Autodesk Fusion 360 part; units mm, degrees
(part 3 of 3)
equation "oledW = 35.4 mm" comment "Handson Technology DSP1170 PCB width, page 2"
equation "oledH = 33.5 mm" comment "Handson Technology DSP1170 PCB height, page 2"
equation "oledT = 1.2 mm" comment "Nominal OLED PCB thickness"
equation "oledHoleX = oledW - 5 mm" comment "Handson drawing hole centers 2.5 mm from each side"
equation "oledHoleY = oledH - 5 mm" comment "Handson drawing hole centers 2.5 mm from each end"
equation "oledHoleD = 2.5 mm" comment "Handson drawing mounting hole radius 1.25 mm"
equation "oledHoleCY = 0 mm" comment "Handson centered mounting-hole rectangle"
equation "oledGlassW = 34.5 mm" comment "Approximate glass width from Handson page 2 projection"
equation "oledGlassH = 23 mm" comment "Approximate glass height from Handson page 2 projection"
equation "oledGlassY = 0 mm" comment "Centered from Handson page 2 projection"
equation "oledGlassStack = 1.9 mm" comment "Glass plus adhesive above PCB, nominal"
equation "oledActiveW = 29.42 mm" comment "SH1106 1.3-inch nominal active width"
equation "oledActiveH = 14.70 mm" comment "SH1106 1.3-inch nominal active height"
equation "oledActiveY = -1.8 mm" comment "Estimated visible area offset from Handson front image"
equation "oledPadPitch = 2.54 mm" comment "Nominal pitch from Handson four-pad row"
equation "oledPadY = oledH / 2 - 2 mm" comment "Handson pad row center 2 mm from PCB top"
equation "wireStack = 1 mm" comment "User estimate for soldered wire protrusion"
equation "windowW = oledActiveW + 1.8 mm" comment "Pixel mask includes alignment allowance"
equation "windowH = oledActiveH + 1.8 mm" comment "Pixel mask includes alignment allowance"
equation "screenSetback = 3.2 mm" comment "Deeper sloped reveal for long screws, PCB unchanged in XY"
equation "glassGap = 0.2 mm" comment "Equals setback for full through-opening around glass"
equation "glassXYGap = 0.30 mm" comment "Clearance around glass edges"
equation "wall = 1.6 mm" comment "Outer shell wall thickness"
equation "boardGap = 0.25 mm" comment "ESP32 PCB end clearance per side"
equation "oledSideGap = 0.25 mm" comment "OLED PCB to wall clearance per side"
equation "caseW = espL + 2 * wall + 2 * boardGap" comment "Width set by the ESP32 and shell"
equation "caseH = oledH + 2 * wall + 2 * oledSideGap" comment "Height set by OLED and shell"
equation "caseD = 18.55 mm" comment "Allows stock screw range 6-8 mm under head above the ESP32"
equation "frontSkin = 4.6 mm" comment "Extra blind-pilot depth accommodates both interpretations of reported 8 mm screw height"
equation "rearT = 1.55 mm" comment "Rear plate thickness and assembly seam"
equation "cornerR = 2.8 mm" comment "Matched outer corners"
equation "frontEdgeR = 0.5 mm" comment "Front outside roundover"
equation "rearEdgeR = 0.35 mm" comment "Rear outside roundover"
equation "m2Pilot = 1.7 mm" comment "Trial diameter for threads formed in printed plastic"
equation "m2Clear = 2.35 mm" comment "Screw clearance through rear supports"
equation "m2HeadD = 4.3 mm" comment "Recess diameter allowance, check stock head"
equation "m2HeadZ = 2.85 mm" comment "Deeper rear head seat allows 2-4 mm thread engagement for 6-8 mm shanks"
equation "m2Length = 8 mm" comment "Nominal screw length under head"
equation "m2TipGap = 0.45 mm" comment "Blind screw hole tip clearance"
equation "m2BossD = 5.2 mm" comment "Front screw boss diameter"
equation "espPostD = 4.4 mm" comment "Rear spacer fits the PCB mounting land"
equation "espFootD = 6 mm" comment "Wider screw recess floor support"
equation "espFootZ = 3.55 mm" comment "Thicker counterbore roof, switch-side clearance removed locally"
equation "espClampGap = 0.1 mm" comment "Avoids crushing ESP PCB at seam, shim if needed"
equation "oledPadD = 4.6 mm" comment "Four load-bearing bosses around the actual OLED mounting holes"
equation "oledSeat = caseD - screenSetback - oledGlassStack" comment "OLED PCB front face"
equation "oledRear = oledSeat - oledT" comment "OLED PCB back, nominal 2.5 mm from ESP PCB"
equation "clampGap = 0.12 mm" comment "Positive closing clearance; thin compressible shim as needed"
equation "clampX = oledW / 2 - 4.9 mm" comment "OLED clamp pads near PCB corners clear central header"
equation "clampW = 4.8 mm" comment "Width of OLED retaining fingers"
equation "clampInnerY = oledH / 2 - 1.8 mm" comment "Clamp overlap with OLED PCB"
equation "clampOuterY = caseH / 2 - wall - 0.24 mm" comment "Clamp outer wall clearance"
equation "keyGap = 0.25 mm" comment "Rear locating key to shell clearance"
equation "d79 = rearT"
equation "d81 = -( -caseW / 2 )"
equation "d82 = -( -caseH / 2 )"
equation "d83 = caseW"
equation "d84 = caseH"
equation "d85 = caseD - rearT"
equation "d88 = cornerR"
equation "d90 = frontEdgeR"
equation "d91 = rearT"
equation "d93 = -( -caseW / 2 + wall )"
equation "d94 = -( -caseH / 2 + wall )"
equation "d95 = caseW - 2 * wall"
equation "d96 = caseH - 2 * wall"
equation "d97 = caseD - frontSkin - rearT"
equation "d100 = cornerR - wall"
equation "d101 = caseD - frontSkin"
equation "d103 = -( -oledGlassW / 2 - glassXYGap )"
equation "d104 = -( oledGlassY - oledGlassH / 2 - glassXYGap )"
equation "d105 = oledGlassW + 2 * glassXYGap"
equation "d106 = oledGlassH + 2 * glassXYGap"
equation "d107 = frontSkin - screenSetback + glassGap"
equation "d109 = caseD - screenSetback + glassGap"
equation "d111 = -( -windowW / 2 )"
equation "d112 = -( oledActiveY - windowH / 2 )"
equation "d113 = windowW"
equation "d114 = windowH"
equation "d117 = oledSeat"
equation "d119 = -( -oledHoleX / 2 )"
equation "d120 = -( oledHoleCY - oledHoleY / 2 )"
equation "d121 = oledPadD"
equation "d122 = caseD - frontSkin - oledSeat"
equation "d124 = oledSeat"
equation "d126 = -( -oledHoleX / 2 )"
equation "d127 = ( oledHoleCY + oledHoleY / 2 )"
equation "d128 = oledPadD"
equation "d129 = caseD - frontSkin - oledSeat"
equation "d131 = oledSeat"
equation "d133 = ( oledHoleX / 2 )"
equation "d134 = -( oledHoleCY - oledHoleY / 2 )"
equation "d135 = oledPadD"
equation "d136 = caseD - frontSkin - oledSeat"
equation "d138 = oledSeat"
equation "d140 = ( oledHoleX / 2 )"
equation "d141 = ( oledHoleCY + oledHoleY / 2 )"
equation "d142 = oledPadD"
equation "d143 = caseD - frontSkin - oledSeat"
equation "d145 = oledRear - 0.35 mm"
equation "d147 = -( -oledW / 2 - oledSideGap - 1.5 mm )"
equation "d148 = -( -10.5 mm )"
equation "d151 = caseD - frontSkin - oledRear + 0.35 mm"
equation "d153 = oledRear - 0.35 mm"
equation "d155 = -( -oledW / 2 - oledSideGap - 1.5 mm )"
equation "d156 = ( 6.5 mm )"
equation "d159 = caseD - frontSkin - oledRear + 0.35 mm"
equation "d161 = oledRear - 0.35 mm"
equation "d163 = ( oledW / 2 + oledSideGap )"
equation "d164 = -( -10.5 mm )"
equation "d167 = caseD - frontSkin - oledRear + 0.35 mm"
equation "d169 = oledRear - 0.35 mm"
equation "d171 = ( oledW / 2 + oledSideGap )"
equation "d172 = ( 6.5 mm )"
equation "d175 = caseD - frontSkin - oledRear + 0.35 mm"
equation "d177 = espBack + espClampGap"
equation "d179 = -( -espHoleX / 2 )"
equation "d180 = -( -espHoleY / 2 )"
equation "d181 = m2BossD"
equation "d182 = caseD - frontSkin - espBack - espClampGap"
equation "d184 = espBack + espClampGap"
equation "d186 = -( -espHoleX / 2 )"
equation "d187 = ( espHoleY / 2 )"
equation "d188 = m2BossD"
equation "d189 = caseD - frontSkin - espBack - espClampGap"
equation "d191 = espBack + espClampGap"
equation "d193 = ( espHoleX / 2 )"
equation "d194 = -( -espHoleY / 2 )"
equation "d195 = m2BossD"
equation "d196 = caseD - frontSkin - espBack - espClampGap"
equation "d198 = espBack + espClampGap"
equation "d200 = ( espHoleX / 2 )"
equation "d201 = ( espHoleY / 2 )"
equation "d202 = m2BossD"
equation "d203 = caseD - frontSkin - espBack - espClampGap"
equation "d205 = espBack + espClampGap"
equation "d207 = -( -caseW / 2 + wall - 0.2 mm )"
equation "d208 = -( -espHoleY / 2 - 1.45 mm )"
equation "d209 = caseW / 2 - wall - espHoleX / 2 + 0.2 mm"
equation "d211 = caseD - frontSkin - espBack - espClampGap"
equation "d213 = espBack + espClampGap"
equation "d215 = -( -caseW / 2 + wall - 0.2 mm )"
equation "d216 = ( espHoleY / 2 - 1.45 mm )"
equation "d217 = caseW / 2 - wall - espHoleX / 2 + 0.2 mm"
equation "d219 = caseD - frontSkin - espBack - espClampGap"
equation "d221 = espBack + espClampGap"
equation "d223 = ( espHoleX / 2 )"
equation "d224 = -( -espHoleY / 2 - 1.45 mm )"
equation "d225 = caseW / 2 - wall - espHoleX / 2 + 0.2 mm"
equation "d227 = caseD - frontSkin - espBack - espClampGap"
equation "d229 = espBack + espClampGap"
equation "d231 = ( espHoleX / 2 )"
equation "d232 = ( espHoleY / 2 - 1.45 mm )"
equation "d233 = caseW / 2 - wall - espHoleX / 2 + 0.2 mm"
equation "d235 = caseD - frontSkin - espBack - espClampGap"
equation "d237 = espBack + espClampGap"
equation "d239 = -( -espHoleX / 2 )"
equation "d240 = -( -espHoleY / 2 )"
equation "d241 = m2Pilot"
equation "d242 = m2HeadZ + m2Length + m2TipGap - espBack - espClampGap"
equation "d244 = espBack + espClampGap"
equation "d246 = -( -espHoleX / 2 )"
equation "d247 = ( espHoleY / 2 )"
equation "d248 = m2Pilot"
equation "d249 = m2HeadZ + m2Length + m2TipGap - espBack - espClampGap"
equation "d251 = espBack + espClampGap"
equation "d253 = ( espHoleX / 2 )"
equation "d254 = -( -espHoleY / 2 )"
equation "d255 = m2Pilot"
equation "d256 = m2HeadZ + m2Length + m2TipGap - espBack - espClampGap"
equation "d258 = espBack + espClampGap"
equation "d260 = ( espHoleX / 2 )"
equation "d261 = ( espHoleY / 2 )"
equation "d262 = m2Pilot"
equation "d263 = m2HeadZ + m2Length + m2TipGap - espBack - espClampGap"
equation "d265 = rearT"
equation "d267 = ( caseW / 2 - wall - 1.7 mm )"
equation "d268 = -( usbY - usbOpeningW / 2 )"
equation "d269 = wall + 2.7 mm"
equation "d270 = usbOpeningW"
equation "d271 = usbSlotTop - rearT"
equation "d273 = -( -caseW / 2 )"
equation "d274 = -( -caseH / 2 )"
equation "d275 = caseW"
equation "d276 = caseH"
equation "d277 = rearT"
equation "d280 = cornerR"
equation "d282 = rearEdgeR"
equation "d283 = rearT"
equation "d285 = -( -espHoleX / 2 )"
equation "d286 = -( -espHoleY / 2 )"
equation "d287 = espFootD"
equation "d288 = espFootZ - rearT"
equation "d290 = rearT"
equation "d292 = -( -espHoleX / 2 )"
equation "d293 = ( espHoleY / 2 )"
equation "d294 = espFootD"
equation "d295 = espFootZ - rearT"
equation "d297 = rearT"
equation "d299 = ( espHoleX / 2 )"
equation "d300 = -( -espHoleY / 2 )"
equation "d301 = espFootD"
equation "d302 = espFootZ - rearT"
equation "d304 = rearT"
equation "d306 = ( espHoleX / 2 )"
equation "d307 = ( espHoleY / 2 )"
equation "d308 = espFootD"
equation "d309 = espFootZ - rearT"
equation "d311 = espFootZ"
equation "d313 = -( -espHoleX / 2 )"
equation "d314 = -( -espHoleY / 2 )"
equation "d315 = espPostD"
equation "d316 = espSeat - espFootZ"
equation "d318 = espFootZ"
equation "d320 = -( -espHoleX / 2 )"
equation "d321 = ( espHoleY / 2 )"
equation "d322 = espPostD"
equation "d323 = espSeat - espFootZ"
equation "d325 = espFootZ"
equation "d327 = ( espHoleX / 2 )"
equation "d328 = -( -espHoleY / 2 )"
equation "d329 = espPostD"
equation "d330 = espSeat - espFootZ"
equation "d332 = espFootZ"
equation "d334 = ( espHoleX / 2 )"
equation "d335 = ( espHoleY / 2 )"
equation "d336 = espPostD"
equation "d337 = espSeat - espFootZ"
equation "d339 = -( -espHoleX / 2 )"
equation "d340 = -( -espHoleY / 2 )"
equation "d341 = m2Clear"
equation "d342 = espSeat"
equation "d344 = -( -espHoleX / 2 )"
equation "d345 = ( espHoleY / 2 )"
equation "d346 = m2Clear"
equation "d347 = espSeat"
equation "d349 = ( espHoleX / 2 )"
equation "d350 = -( -espHoleY / 2 )"
equation "d351 = m2Clear"
equation "d352 = espSeat"
equation "d354 = ( espHoleX / 2 )"
equation "d355 = ( espHoleY / 2 )"
equation "d356 = m2Clear"
equation "d357 = espSeat"
equation "d359 = -( -espHoleX / 2 )"
equation "d360 = -( -espHoleY / 2 )"
equation "d361 = m2HeadD"
equation "d362 = m2HeadZ"
equation "d364 = -( -espHoleX / 2 )"
equation "d365 = ( espHoleY / 2 )"
equation "d366 = m2HeadD"
equation "d367 = m2HeadZ"
equation "d369 = ( espHoleX / 2 )"
equation "d370 = -( -espHoleY / 2 )"
equation "d371 = m2HeadD"
equation "d372 = m2HeadZ"
equation "d374 = ( espHoleX / 2 )"
equation "d375 = ( espHoleY / 2 )"
equation "d376 = m2HeadD"
equation "d377 = m2HeadZ"
equation "d379 = rearT"
equation "d381 = ( espL / 2 - bootInset )"
equation "d382 = -( bootY )"
equation "d383 = buttonGuideD"
equation "d384 = espSeat - espButtonH - buttonGap - rearT"
equation "d386 = ( espL / 2 - bootInset )"
equation "d387 = -( bootY )"
equation "d388 = buttonBore"
equation "d389 = espSeat - espButtonH - buttonGap"
equation "d391 = rearT"
equation "d393 = ( espL / 2 - enableInset )"
equation "d394 = ( enableY )"
equation "d395 = buttonGuideD"
equation "d396 = espSeat - espButtonH - buttonGap - rearT"
equation "d398 = ( espL / 2 - enableInset )"
equation "d399 = ( enableY )"
equation "d400 = buttonBore"
equation "d401 = espSeat - espButtonH - buttonGap"
equation "d403 = rearT"
equation "d405 = -( -clampX - clampW / 2 )"
equation "d406 = -( -clampOuterY )"
equation "d407 = clampW"
equation "d408 = clampOuterY - clampInnerY"
equation "d411 = rearT"
equation "d413 = ( clampX - clampW / 2 )"
equation "d414 = -( -clampOuterY )"
equation "d415 = clampW"
equation "d416 = clampOuterY - clampInnerY"
equation "d419 = rearT"
equation "d421 = -( -clampX - clampW / 2 )"
equation "d422 = ( clampInnerY )"
equation "d423 = clampW"
equation "d424 = clampOuterY - clampInnerY"
equation "d427 = rearT"
equation "d429 = ( clampX - clampW / 2 )"
equation "d430 = ( clampInnerY )"
equation "d431 = clampW"
equation "d432 = clampOuterY - clampInnerY"
equation "d435 = rearT"
equation "d437 = -( -18.5 mm )"
equation "d438 = -( -espW / 2 - 1.4 mm )"
equation "d441 = espBack - 0.1 mm - rearT"
equation "d443 = rearT"
equation "d445 = ( 15.5 mm )"
equation "d446 = -( -espW / 2 - 1.4 mm )"
equation "d449 = espBack - 0.1 mm - rearT"
equation "d451 = rearT"
equation "d453 = -( -18.5 mm )"
equation "d454 = ( espW / 2 + 0.2 mm )"
equation "d457 = espBack - 0.1 mm - rearT"
equation "d459 = rearT"
equation "d461 = ( 15.5 mm )"
equation "d462 = ( espW / 2 + 0.2 mm )"
equation "d465 = espBack - 0.1 mm - rearT"
equation "d467 = rearT"
equation "d469 = -( -caseW / 2 + wall + keyGap )"
equation "d470 = caseH / 2 - wall - 1.55 mm"
equation "d475 = rearT"
equation "d477 = -( -caseW / 2 + wall + keyGap )"
equation "d478 = caseH / 2 - wall - 4.15 mm"
equation "d483 = rearT"
equation "d485 = ( caseW / 2 - wall - keyGap - 1.25 mm )"
equation "d486 = caseH / 2 - wall - 1.55 mm"
equation "d491 = rearT"
equation "d493 = ( caseW / 2 - wall - keyGap - 1.25 mm )"
equation "d494 = caseH / 2 - wall - 4.15 mm"
equation "d499 = ( caseW / 2 - usbRearRelief )"
equation "d500 = -( usbY - usbOpeningW / 2 )"
equation "d501 = usbRearRelief + 1 mm"
equation "d502 = usbOpeningW"
equation "d503 = rearT"
equation "d505 = oledRear"
equation "d507 = -( -oledW / 2 )"
equation "d508 = -( -oledH / 2 )"
equation "d509 = oledW"
equation "d510 = oledH"
equation "d511 = oledT"
equation "d513 = oledRear"
equation "d515 = -( -oledHoleX / 2 )"
equation "d516 = -( oledHoleCY - oledHoleY / 2 )"
equation "d517 = oledHoleD"
equation "d518 = oledT"
equation "d520 = oledRear"
equation "d522 = -( -oledHoleX / 2 )"
equation "d523 = ( oledHoleCY + oledHoleY / 2 )"
equation "d524 = oledHoleD"
equation "d525 = oledT"
equation "d527 = oledRear"
equation "d529 = ( oledHoleX / 2 )"
equation "d530 = -( oledHoleCY - oledHoleY / 2 )"
equation "d531 = oledHoleD"
equation "d532 = oledT"
equation "d534 = oledRear"
equation "d536 = ( oledHoleX / 2 )"
equation "d537 = ( oledHoleCY + oledHoleY / 2 )"
equation "d538 = oledHoleD"
equation "d539 = oledT"
equation "d541 = oledSeat"
equation "d543 = -( -oledGlassW / 2 )"
equation "d544 = -( oledGlassY - oledGlassH / 2 )"
equation "d545 = oledGlassW"
equation "d546 = oledGlassH"
equation "d547 = oledGlassStack"
equation "d549 = oledRear - wireStack"
equation "d551 = -( -2 * oledPadPitch )"
equation "d552 = ( oledPadY - 1.2 mm )"
equation "d553 = 4 * oledPadPitch"
equation "d555 = wireStack"
equation "d557 = espSeat"
equation "d559 = -( -espL / 2 )"
equation "d560 = -( -espW / 2 )"
equation "d561 = espL"
equation "d562 = espW"
equation "d563 = espT"
equation "d565 = espSeat"
equation "d567 = -( -espHoleX / 2 )"
equation "d568 = -( -espHoleY / 2 )"
equation "d569 = espHoleD"
equation "d570 = espT"
equation "d572 = espSeat"
equation "d574 = -( -espHoleX / 2 )"
equation "d575 = ( espHoleY / 2 )"
equation "d576 = espHoleD"
equation "d577 = espT"
equation "d579 = espSeat"
equation "d581 = ( espHoleX / 2 )"
equation "d582 = -( -espHoleY / 2 )"
equation "d583 = espHoleD"
equation "d584 = espT"
equation "d586 = espSeat"
equation "d588 = ( espHoleX / 2 )"
equation "d589 = ( espHoleY / 2 )"
equation "d590 = espHoleD"
equation "d591 = espT"
equation "d593 = espSeat - espPartH"
equation "d595 = -( -espL / 2 + espAntennaL )"
equation "d596 = -( -9 mm )"
equation "d597 = 25.5 mm - espAntennaL"
equation "d599 = espPartH"
equation "d601 = espSeat - 0.9 mm"
equation "d603 = -( -espL / 2 )"
equation "d604 = -( -9 mm )"
equation "d605 = espAntennaL"
equation "d609 = espSeat - usbShellH"
equation "d611 = ( espL / 2 - 6.2 mm )"
equation "d612 = -( usbY - usbShellW / 2 )"
equation "d613 = 6.2 mm + usbProtrusion"
equation "d614 = usbShellW"
equation "d615 = usbShellH"
equation "d617 = espSeat - espButtonH"
equation "d619 = ( espL / 2 - bootInset - 1.8 mm )"
equation "d620 = -( bootY - 1.3 mm )"
equation "d623 = espButtonH"
equation "d625 = espSeat - espButtonH"
equation "d627 = ( espL / 2 - enableInset - 1.8 mm )"
equation "d628 = ( enableY - 1.3 mm )"
equation "d631 = espButtonH"
equation "displayBevel = 2.65 mm" comment "45 degree sloped display surround, 0.35 mm straight throat"
equation "oledScrewL = 8 mm" comment "Upper end of 6-8 mm under-head stock design range, not a measured shank"
equation "oledScrewHeadH = 2 mm" comment "Maximum modeled OLED screw head height"
equation "oledScrewHeadD = 4 mm" comment "Maximum modeled OLED screw head diameter"
equation "oledPilotDepth = 4.1 mm" comment "Up to 3.8 mm engagement plus 0.3 mm tip clearance"
equation "d638 = caseD - screenSetback + glassGap"
equation "d640 = -( -windowW / 2 )"
equation "d641 = -( oledActiveY - windowH / 2 )"
equation "d642 = windowW"
equation "d643 = windowH"
equation "d644 = screenSetback - glassGap"
equation "d646 = oledSeat"
equation "d648 = -( -oledHoleX / 2 )"
equation "d649 = -( oledHoleCY - oledHoleY / 2 )"
equation "d650 = m2Pilot"
equation "d651 = oledPilotDepth"
equation "d653 = oledSeat"
equation "d655 = -( -oledHoleX / 2 )"
equation "d656 = ( oledHoleCY + oledHoleY / 2 )"
equation "d657 = m2Pilot"
equation "d658 = oledPilotDepth"
equation "d660 = oledSeat"
equation "d662 = ( oledHoleX / 2 )"
equation "d663 = -( oledHoleCY - oledHoleY / 2 )"
equation "d664 = m2Pilot"
equation "d665 = oledPilotDepth"
equation "d667 = oledSeat"
equation "d669 = ( oledHoleX / 2 )"
equation "d670 = ( oledHoleCY + oledHoleY / 2 )"
equation "d671 = m2Pilot"
equation "d672 = oledPilotDepth"
equation "d674 = displayBevel"
equation "d675 = oledRear - oledSpacerH - oledScrewHeadH"
equation "d677 = -( -oledHoleX / 2 )"
equation "d678 = -( oledHoleCY - oledHoleY / 2 )"
equation "d679 = oledScrewHeadD"
equation "d680 = oledScrewHeadH"
equation "d682 = oledRear - oledSpacerH"
equation "d684 = -( -oledHoleX / 2 )"
equation "d685 = -( oledHoleCY - oledHoleY / 2 )"
equation "d687 = oledScrewL"
equation "d689 = oledRear - oledSpacerH - oledScrewHeadH"
equation "d691 = -( -oledHoleX / 2 )"
equation "d692 = ( oledHoleCY + oledHoleY / 2 )"
equation "d693 = oledScrewHeadD"
equation "d694 = oledScrewHeadH"
equation "d696 = oledRear - oledSpacerH"
equation "d698 = -( -oledHoleX / 2 )"
equation "d699 = ( oledHoleCY + oledHoleY / 2 )"
equation "d701 = oledScrewL"
equation "d703 = oledRear - oledSpacerH - oledScrewHeadH"
equation "d705 = ( oledHoleX / 2 )"
equation "d706 = -( oledHoleCY - oledHoleY / 2 )"
equation "d707 = oledScrewHeadD"
equation "d708 = oledScrewHeadH"
equation "d710 = oledRear - oledSpacerH"
equation "d712 = ( oledHoleX / 2 )"
equation "d713 = -( oledHoleCY - oledHoleY / 2 )"
equation "d715 = oledScrewL"
equation "d717 = oledRear - oledSpacerH - oledScrewHeadH"
equation "d719 = ( oledHoleX / 2 )"
equation "d720 = ( oledHoleCY + oledHoleY / 2 )"
equation "d721 = oledScrewHeadD"
equation "d722 = oledScrewHeadH"
equation "d724 = oledRear - oledSpacerH"
equation "d726 = ( oledHoleX / 2 )"
equation "d727 = ( oledHoleCY + oledHoleY / 2 )"
equation "d729 = oledScrewL"
equation "oledSpacerH = 3 mm" comment "Separate printed spacers beneath PCB for long stock screws"
equation "oledSpacerD = 4.6 mm" comment "Spacer mounting land diameter"
equation "oledSpacerBarH = 1.4 mm" comment "Connects a pair of spacers into one printable rail"
equation "wireFrontH = oledGlassStack" comment "User says cable connections rise approximately as high as glass"
equation "wireRoofGap = 0.3 mm" comment "Clearance above front-facing soldered wires"
equation "wirePocketW = 13 mm" comment "Four 2.54 mm-pitch wires plus side clearance"
equation "wirePocketY = oledGlassY + oledGlassH / 2 - 0.2 mm" comment "Joins cable clearance to glass recess without pinching the bend"
equation "wirePocketEndY = oledH / 2 + 0.25 mm" comment "Wire relief terminates inside shell side wall"
equation "d739 = oledRear - oledSpacerH"
equation "d741 = -( -oledHoleX / 2 )"
equation "d742 = -( oledHoleCY - oledHoleY / 2 )"
equation "d744 = oledHoleY"
equation "d745 = oledSpacerBarH"
equation "d747 = oledRear - oledSpacerH"
equation "d749 = -( -1 * oledHoleX / 2 )"
equation "d750 = -( oledHoleCY - oledHoleY / 2 )"
equation "d751 = oledSpacerD"
equation "d752 = oledSpacerH"
equation "d754 = oledRear - oledSpacerH"
equation "d756 = -( -1 * oledHoleX / 2 )"
equation "d757 = ( oledHoleCY + oledHoleY / 2 )"
equation "d758 = oledSpacerD"
equation "d759 = oledSpacerH"
equation "d761 = oledRear - oledSpacerH"
equation "d763 = -( -1 * oledHoleX / 2 )"
equation "d764 = -( oledHoleCY - oledHoleY / 2 )"
equation "d765 = m2Clear"
equation "d766 = oledSpacerH"
equation "d768 = oledRear - oledSpacerH"
equation "d770 = -( -1 * oledHoleX / 2 )"
equation "d771 = ( oledHoleCY + oledHoleY / 2 )"
equation "d772 = m2Clear"
equation "d773 = oledSpacerH"
equation "d775 = oledRear - oledSpacerH"
equation "d777 = ( oledHoleX / 2 - 2.1 mm )"
equation "d778 = -( oledHoleCY - oledHoleY / 2 )"
equation "d780 = oledHoleY"
equation "d781 = oledSpacerBarH"
equation "d783 = oledRear - oledSpacerH"
equation "d785 = ( 1 * oledHoleX / 2 )"
equation "d786 = -( oledHoleCY - oledHoleY / 2 )"
equation "d787 = oledSpacerD"
equation "d788 = oledSpacerH"
equation "d790 = oledRear - oledSpacerH"
equation "d792 = ( 1 * oledHoleX / 2 )"
equation "d793 = ( oledHoleCY + oledHoleY / 2 )"
equation "d794 = oledSpacerD"
equation "d795 = oledSpacerH"
equation "d797 = oledRear - oledSpacerH"
equation "d799 = ( 1 * oledHoleX / 2 )"
equation "d800 = -( oledHoleCY - oledHoleY / 2 )"
equation "d801 = m2Clear"
equation "d802 = oledSpacerH"
equation "d804 = oledRear - oledSpacerH"
equation "d806 = ( 1 * oledHoleX / 2 )"
equation "d807 = ( oledHoleCY + oledHoleY / 2 )"
equation "d808 = m2Clear"
equation "d809 = oledSpacerH"
equation "d811 = caseD - frontSkin"
equation "d813 = -( -wirePocketW / 2 )"
equation "d814 = ( wirePocketY )"
equation "d815 = wirePocketW"
equation "d816 = wirePocketEndY - wirePocketY"
equation "d817 = oledSeat + wireFrontH + wireRoofGap - caseD + frontSkin"
equation "d819 = oledSeat"
equation "d821 = -( -2 * oledPadPitch )"
equation "d822 = ( oledPadY - 1.2 mm )"
equation "d823 = 4 * oledPadPitch"
equation "d825 = wireFrontH"
equation "d827 = espSeat - espButtonH - 0.05 mm"
equation "d829 = ( espL / 2 - bootInset - 2.2 mm )"
equation "d830 = -( bootY - 1.55 mm )"
equation "d833 = espFootZ - espSeat + espButtonH + 0.05 mm"
equation "d835 = espSeat - espButtonH - 0.05 mm"
equation "d837 = ( espL / 2 - bootInset - 2.2 mm )"
equation "d838 = ( enableY - 1.55 mm )"
equation "d841 = espFootZ - espSeat + espButtonH + 0.05 mm"
equation "d843 = m2HeadZ - oledScrewHeadH"
equation "d845 = -( -espHoleX / 2 )"
equation "d846 = -( -espHoleY / 2 )"
equation "d847 = oledScrewHeadD"
equation "d848 = oledScrewHeadH"
equation "d850 = m2HeadZ"
equation "d852 = -( -espHoleX / 2 )"
equation "d853 = -( -espHoleY / 2 )"
equation "d855 = m2Length"
equation "d857 = m2HeadZ - oledScrewHeadH"
equation "d859 = -( -espHoleX / 2 )"
equation "d860 = ( espHoleY / 2 )"
equation "d861 = oledScrewHeadD"
equation "d862 = oledScrewHeadH"
equation "d864 = m2HeadZ"
equation "d866 = -( -espHoleX / 2 )"
equation "d867 = ( espHoleY / 2 )"
equation "d869 = m2Length"
equation "d871 = m2HeadZ - oledScrewHeadH"
equation "d873 = ( espHoleX / 2 )"
equation "d874 = -( -espHoleY / 2 )"
equation "d875 = oledScrewHeadD"
equation "d876 = oledScrewHeadH"
equation "d878 = m2HeadZ"
equation "d880 = ( espHoleX / 2 )"
equation "d881 = -( -espHoleY / 2 )"
equation "d883 = m2Length"
equation "d885 = m2HeadZ - oledScrewHeadH"
equation "d887 = ( espHoleX / 2 )"
equation "d888 = ( espHoleY / 2 )"
equation "d889 = oledScrewHeadD"
equation "d890 = oledScrewHeadH"
equation "d892 = m2HeadZ"
equation "d894 = ( espHoleX / 2 )"
equation "d895 = ( espHoleY / 2 )"
equation "d897 = m2Length"
named bodies: "Beveled front with OLED mounting bosses", "Rear cover with ESP32 mounting seats", "Nominal OLED PCB", "Nominal OLED glass", "OLED four-wire clearance envelope", "Nominal ESP32 PCB", "ESP32-WROOM shield envelope", "ESP32-WROOM antenna laminate", "USB-C receptacle envelope", "BOOT switch envelope", "EN switch envelope", "M2 stock OLED screw 1", "M2 stock OLED screw 2", "M2 stock OLED screw 3", "M2 stock OLED screw 4", "Printed OLED spacer rail 1", "Printed OLED spacer rail 2", "Front cable envelope - glass-height allowance", "M2 stock rear screw 1", "M2 stock rear screw 2", "M2 stock rear screw 3", "M2 stock rear screw 4"
